toytalker_mini_v0.6 (Autodesk Fusion 360 design; units mm, degrees)
part number: 2026-11-09-18-38-09-619
Autodesk Fusion 360 part; units mm, degrees
ref_plane "作業平面1" through (0, 0, 0) normal (0, 0, 1) x (1, 0, 0)
sketch "スケッチ1" plane through (0, 0, 0) normal (0, 0, 1) x (1, 0, 0)
  line L0 (-1.5, -1.5) -> (41.5, -1.5)
  line L1 (41.5, -1.5) -> (41.5, 41.5)
  line L2 (41.5, 41.5) -> (-1.5, 41.5)
  line L3 (-1.5, 41.5) -> (-1.5, -1.5)
  dimension "board" = 40
  dimension "gap" = 0.2
  dimension "wall" = 1.3
  dimension "inner_h" = 9.4
  dimension "board_top" = 5
  dimension "lid_t" = 1.3
  dimension "corner_r" = 1.3
  dimension "hook_len" = 2.6
  dimension "hook_w" = 6
  dimension "hook_t" = 0.8
  dimension "barb" = 0.4
  dimension "usb_w" = 9.6
  dimension "usb_h" = 3.8
  dimension "sw_slot_l" = 3.4
  dimension "sw_slot_h" = 1
  dimension "btn_nub_d" = 3
  dimension "btn_clear" = 0.2
  dimension "btn_tongue_t" = 0.6
  dimension "spk_hole_d" = 1.6
  dimension "strap_hole_d" = 2
extrude "ç®±_æ¼ãåºã" add sketch "スケッチ1" along normal blind 10.7 makes body 1
fillet "ç®±_è§R" radius 1.3 4 edges at (-1.5, 41.5, 5.35) (41.5, 41.5, 5.35) (41.5, -1.5, 5.35) (-1.5, -1.5, 5.35) on bodies 1
shell "ç®±_ã·ã§ã«" thickness 1.3 removed faces 1 at (13.2667, 27.1667, 10.7) on bodies 1
sketch "スケッチ2" plane through (0, 0, 0) normal (1, 0, 0) x (0, 0, -1)
  line L0 (-6.065, 16.375) -> (-9.865, 16.375)
  line L1 (-9.865, 16.375) -> (-9.865, 25.975)
  line L2 (-9.865, 25.975) -> (-6.065, 25.975)
  line L3 (-6.065, 25.975) -> (-6.065, 16.375)
extrude "USBç©´ (1)" cut sketch "スケッチ2" against normal blind 2 bodies 1
sketch "スケッチ3" plane through (0, 0, 0) normal (0, 1, 0) x (1, 0, 0)
  line L0 (3.8, -6.2) -> (7.2, -6.2)
  line L1 (7.2, -6.2) -> (7.2, -7.2)
  line L2 (7.2, -7.2) -> (3.8, -7.2)
  line L3 (3.8, -7.2) -> (3.8, -6.2)
extrude "ã¹ã¤ããç©´ (1)" cut sketch "スケッチ3" along normal blind 42 bodies 1
sketch "スケッチ4" plane through (0, 0, 0) normal (0, 1, 0) x (1, 0, 0)
  line L0 (2.5, -5.4) -> (8.5, -5.4)
  line L1 (8.5, -5.4) -> (8.5, -8)
  line L2 (8.5, -8) -> (2.5, -8)
  line L3 (2.5, -8) -> (2.5, -5.4)
extrude "ã¹ã¤ãããã¼ã¿ (1)" cut sketch "スケッチ4" along normal blind 0.6 from surface at 41 bodies 1
ref_plane "作業平面2" through (0, 0, 8) normal (0, 0, 1) x (1, 0, 0)
sketch "スケッチ5" plane through (0, 0, 8) normal (0, 0, 1) x (1, 0, 0)
  line L0 (-0.6, 28.8) -> (-0.2, 28.8)
  line L1 (-0.2, 28.8) -> (-0.2, 35.2)
  line L2 (-0.2, 35.2) -> (-0.6, 35.2)
  line L3 (-0.6, 35.2) -> (-0.6, 28.8)
  line L4 (40.2, 16.8) -> (40.6, 16.8)
  line L5 (40.6, 16.8) -> (40.6, 23.2)
  line L6 (40.6, 23.2) -> (40.2, 23.2)
  line L7 (40.2, 23.2) -> (40.2, 16.8)
  line L8 (16.8, 40.2) -> (23.2, 40.2)
  line L9 (23.2, 40.2) -> (23.2, 40.6)
  line L10 (23.2, 40.6) -> (16.8, 40.6)
  line L11 (16.8, 40.6) -> (16.8, 40.2)
  line L12 (4.8, -0.6) -> (11.2, -0.6)
  line L13 (11.2, -0.6) -> (11.2, -0.2)
  line L14 (11.2, -0.2) -> (4.8, -0.2)
  line L15 (4.8, -0.2) -> (4.8, -0.6)
extrude "çªã®æº (1)" cut sketch "スケッチ5" along normal blind 0.8 bodies 1
ref_plane "作業平面3" through (0, 0, 9.9) normal (0, 0, 1) x (1, 0, 0)
sketch "スケッチ6" plane through (0, 0, 9.9) normal (0, 0, 1) x (1, 0, 0)
  line L0 (26, -1.55) -> (34, -1.55)
  line L1 (34, -1.55) -> (34, -0.15)
  line L2 (34, -0.15) -> (26, -0.15)
  line L3 (26, -0.15) -> (26, -1.55)
extrude "ææãã (1)" cut sketch "スケッチ6" along normal blind 0.85 bodies 1
ref_plane "作業平面4" through (0, 0, 4.5) normal (0, 0, 1) x (1, 0, 0)
sketch "スケッチ7" plane through (0, 0, 4.5) normal (0, 0, 1) x (1, 0, 0)
  line L0 (41.3, 16) -> (47, 16)
  line L1 (47, 16) -> (47, 24)
  line L2 (47, 24) -> (41.3, 24)
  line L3 (41.3, 24) -> (41.3, 16)
extrude "åãå\u0085· (1)" add sketch "スケッチ7" along normal blind 3 bodies 1
fillet "åãå\u0085·_å\u0085ç«¯R" radius 1.4 2 edges at (47, 20, 7.5) (47, 20, 4.5) on bodies 1
sketch "スケッチ8" plane through (0, 0, 0) normal (0, 1, 0) x (1, 0, 0)
  circle A0 centre (44.8, -6) radius 1
extrude "åãç©´ (1)" cut sketch "スケッチ8" along normal blind 10 from surface at 15 bodies 1
ref_plane "作業平面5" through (0, 0, 10.7) normal (0, 0, 1) x (1, 0, 0)
sketch "スケッチ9" plane through (0, 0, 10.7) normal (0, 0, 1) x (1, 0, 0)
  line L0 (-1.5, -1.5) -> (41.5, -1.5)
  line L1 (41.5, -1.5) -> (41.5, 41.5)
  line L2 (41.5, 41.5) -> (-1.5, 41.5)
  line L3 (-1.5, 41.5) -> (-1.5, -1.5)
extrude "è_æ¼ãåºã" add sketch "スケッチ9" along normal blind 1.3 separate body makes body 2
fillet "è_è§R" radius 1.3 4 edges at (-1.5, 41.5, 11.35) (41.5, 41.5, 11.35) (41.5, -1.5, 11.35) (-1.5, -1.5, 11.35) on bodies 2
fillet "è_ä¸é¢R" radius 0.6 8 edges at (-1.1192, -1.1192, 12) (-1.5, 20, 12) (20, -1.5, 12) (41.1192, -1.1192, 12) (41.5, 20, 12) (41.1192, 41.1192, 12) (20, 41.5, 12) (-1.1192, 41.1192, 12) on bodies 2
ref_plane "作業平面6" through (0, 0, 10.7) normal (0, 0, 1) x (1, 0, 0)
sketch "スケッチ10" plane through (0, 0, 10.7) normal (0, 0, 1) x (1, 0, 0)
  line L0 (12.4, 16.9) -> (23.4, 16.9)
  line L1 (23.4, 16.9) -> (23.4, 30.4)
  line L2 (23.4, 30.4) -> (12.4, 30.4)
  line L3 (12.4, 30.4) -> (12.4, 16.9)
extrude "ãã¿ã³_èè (1)" cut sketch "スケッチ10" along normal blind 0.7 bodies 2
ref_plane "作業平面7" through (0, 0, 10.7) normal (0, 0, 1) x (1, 0, 0)
sketch "スケッチ11" plane through (0, 0, 10.7) normal (0, 0, 1) x (1, 0, 0)
  line L0 (12.4, 16.9) -> (12.9, 16.9)
  line L1 (12.9, 16.9) -> (12.9, 29.4)
  line L2 (12.9, 29.4) -> (12.4, 29.4)
  line L3 (12.4, 29.4) -> (12.4, 16.9)
  line L4 (22.9, 16.9) -> (23.4, 16.9)
  line L5 (23.4, 16.9) -> (23.4, 29.4)
  line L6 (23.4, 29.4) -> (22.9, 29.4)
  line L7 (22.9, 29.4) -> (22.9, 16.9)
  line L8 (12.9, 16.9) -> (22.9, 16.9)
  line L9 (22.9, 16.9) -> (22.9, 17.4)
  line L10 (22.9, 17.4) -> (12.9, 17.4)
  line L11 (12.9, 17.4) -> (12.9, 16.9)
extrude "ãã¿ã³_ã¹ãªãã (1)" cut sketch "スケッチ11" along normal blind 1.35 bodies 2
ref_plane "作業平面8" through (0, 0, 9) normal (0, 0, 1) x (1, 0, 0)
sketch "スケッチ12" plane through (0, 0, 9) normal (0, 0, 1) x (1, 0, 0)
  circle A0 centre (17.9, 19.4) radius 1.5
extrude "ãã¿ã³_çªèµ· (1)" add sketch "スケッチ12" along normal blind 2.4 bodies 2
ref_plane "作業平面9" through (0, 0, 10.7) normal (0, 0, 1) x (1, 0, 0)
sketch "スケッチ13" plane through (0, 0, 10.7) normal (0, 0, 1) x (1, 0, 0)
  circle A0 centre (25, 6) radius 0.8
  circle A1 centre (25, 10.5) radius 0.8
  circle A2 centre (25, 15) radius 0.8
  circle A3 centre (29.5, 6) radius 0.8
  circle A4 centre (29.5, 10.5) radius 0.8
  circle A5 centre (29.5, 15) radius 0.8
  circle A6 centre (34, 6) radius 0.8
  circle A7 centre (34, 10.5) radius 0.8
  circle A8 centre (34, 15) radius 0.8
extrude "é³æãç©´ (1)" cut sketch "スケッチ13" along normal blind 1.35 bodies 2
ref_plane "作業平面10" through (0, 0, 10.7) normal (0, 0, 1) x (1, 0, 0)
sketch "スケッチ14" plane through (0, 0, 10.7) normal (0, 0, 1) x (1, 0, 0)
  line L0 (-0.1, 29) -> (0.7, 29)
  line L1 (0.7, 29) -> (0.7, 35)
  line L2 (0.7, 35) -> (-0.1, 35)
  line L3 (-0.1, 35) -> (-0.1, 29)
  line L4 (39.3, 17) -> (40.1, 17)
  line L5 (40.1, 17) -> (40.1, 23)
  line L6 (40.1, 23) -> (39.3, 23)
  line L7 (39.3, 23) -> (39.3, 17)
  line L8 (17, 39.3) -> (23, 39.3)
  line L9 (23, 39.3) -> (23, 40.1)
  line L10 (23, 40.1) -> (17, 40.1)
  line L11 (17, 40.1) -> (17, 39.3)
  line L12 (5, -0.1) -> (11, -0.1)
  line L13 (11, -0.1) -> (11, 0.7)
  line L14 (11, 0.7) -> (5, 0.7)
  line L15 (5, 0.7) -> (5, -0.1)
extrude "çª (1)" add sketch "スケッチ14" against normal blind 2.6 bodies 2
ref_plane "作業平面11" through (0, 0, 8.1) normal (0, 0, 1) x (1, 0, 0)
sketch "スケッチ15" plane through (0, 0, 8.1) normal (0, 0, 1) x (1, 0, 0)
  line L0 (-0.6, 29) -> (-0.1, 29)
  line L1 (-0.1, 29) -> (-0.1, 35)
  line L2 (-0.1, 35) -> (-0.6, 35)
  line L3 (-0.6, 35) -> (-0.6, 29)
  line L4 (40.1, 17) -> (40.6, 17)
  line L5 (40.6, 17) -> (40.6, 23)
  line L6 (40.6, 23) -> (40.1, 23)
  line L7 (40.1, 23) -> (40.1, 17)
  line L8 (17, 40.1) -> (23, 40.1)
  line L9 (23, 40.1) -> (23, 40.6)
  line L10 (23, 40.6) -> (17, 40.6)
  line L11 (17, 40.6) -> (17, 40.1)
  line L12 (5, -0.6) -> (11, -0.6)
  line L13 (11, -0.6) -> (11, -0.1)
  line L14 (11, -0.1) -> (5, -0.1)
  line L15 (5, -0.1) -> (5, -0.6)
extrude "çªã®è¿ã (1)" add sketch "スケッチ15" along normal blind 0.6 bodies 2
chamfer "面取り1" distance 0.35 angle 45 4 edges at (8, -0.6, 8.1) (-0.6, 32, 8.1) (40.6, 20, 8.1) (20, 40.6, 8.1) on bodies 2
equation "board = 40.0 mm" comment "åºæ¿ã®ä¸è¾ºï¼v0.3ã40Ã40ï¼"
equation "gap = 0.2 mm" comment "åºæ¿ã¨åå£ã®ããéï¼çå´ï¼"
equation "wall = 1.3 mm" comment "å´å£ã¨åºã®åã"
equation "inner_h = 9.4 mm" comment "åå¯¸ã®é«ãï¼é»æ± 3ï¼ã¯ãã·ã§ã³1ï¼åºæ¿1ï¼é¨å4ï¼ä½è£0.4ï¼"
equation "board_top = 5.0 mm" comment "ååºããåºæ¿ä¸é¢ã¾ã§ï¼é»æ± 3ï¼ã¯ãã·ã§ã³1ï¼åºæ¿1ï¼"
equation "lid_t = 1.3 mm" comment "èã®åã"
equation "corner_r = 1.3 mm" comment "å¤å½¢ã®è§ã®ä¸¸ã¿"
equation "hook_len = 2.6 mm" comment "èã®çªã®é·ãï¼èã®è£ããï¼"
equation "hook_w = 6.0 mm" comment "èã®çªã®å¹"
equation "hook_t = 0.8 mm" comment "èã®çªã®åã"
equation "barb = 0.4 mm" comment "çªã®æããï¼æºã®æ·±ãï¼"
equation "usb_w = 9.6 mm" comment "USB-C ç©´ã®å¹"
equation "usb_h = 3.8 mm" comment "USB-C ç©´ã®é«ã"
equation "sw_slot_l = 3.4 mm" comment "ã¹ã©ã¤ãã¹ã¤ããã®ç©´ã®é·ãï¼ãã1.2ï¼åã1.4ï¼ä½è£ï¼"
equation "sw_slot_h = 1.0 mm" comment "ã¹ã©ã¤ãã¹ã¤ããã®ç©´ã®é«ã"
equation "btn_nub_d = 3.0 mm" comment "ãã¿ã³çªèµ·ã®ç´å¾"
equation "btn_clear = 0.2 mm" comment "ãã¿ã³çªèµ·ã¨æ¼ãå­ã®ããéï¼å¸¸æï¼"
equation "btn_tongue_t = 0.6 mm" comment "ãã¿ã³æ¿ã°ã­ã®åã"
equation "spk_hole_d = 1.6 mm" comment "èã®é³æãç©´ã®ç´å¾"
equation "strap_hole_d = 2.0 mm" comment "åãç©´ã®ç´å¾"
equation "d26 = wall"
named bodies: "ç®±"
